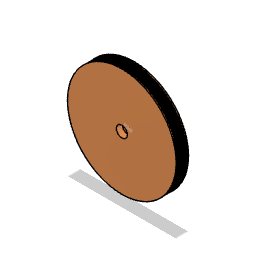
_PULLEY v4.d1a926d5-162d-4901-994e-79e1f1fda4be_LV0.f3d v1 (Autodesk Fusion 360 design; units mm, degrees)
Autodesk Fusion 360 part; units mm, degrees
sketch "Profile" plane through (0, 0, 0) normal (0, 0, 1) x (1, 0, 0) in component "GT2-Pulley"
  circle A0 centre (0, 0) radius 63.662 construction
  circle A1 centre (0, 0) radius 62.658 construction
  line L0 (0, 0) -> (0, 63.662) construction
  line L1 (0, 0) -> (1, 63.6541) construction
  line L2 (0, 0) -> (1.3999, 63.6466) construction
  circle A2 centre (0, 0) radius 63.408 construction
  arc A3 (0.5642, 62.8528) -> (0.9842, 62.6502) centre (0.9929, 63.2052) ccw
  circle A4 centre (0, 0) radius 63.258 construction
  arc A5 (0.4012, 63.2751) -> (0.4738, 63.0018) centre (1.3943, 63.3926) ccw
  arc A6 (0.2529, 63.4075) -> (0, 63.408) centre (0, 0) ccw
  arc A7 (0.4012, 63.2751) -> (0.2529, 63.4075) centre (0.2523, 63.2575) ccw
  arc A8 (0, 63.408) -> (-0.2529, 63.4075) centre (0, 0) ccw
  arc A9 (-0.2529, 63.4075) -> (-0.4012, 63.2751) centre (-0.2523, 63.2575) ccw
  arc A10 (-0.4738, 63.0018) -> (-0.4012, 63.2751) centre (-1.3943, 63.3926) ccw
  arc A11 (-0.9842, 62.6502) -> (-0.5642, 62.8528) centre (-0.9929, 63.2052) ccw
  arc A12 (0.9842, 62.6502) -> (-0.9842, 62.6502) centre (0, 0) ccw
  arc A13 (0.4738, 63.0018) -> (0.5642, 62.8528) centre (1.0358, 63.2404) ccw
  arc A14 (-0.5642, 62.8528) -> (-0.4738, 63.0018) centre (-1.0358, 63.2404) ccw
  point P0 (0.9842, 62.6502)
  point P1 (1.3943, 63.3926)
  point P2 (0, 63.408)
  dimension "d15_2" = 127.324
  dimension "d16_2" = 0.9
  dimension "d17_2" = 0.36
  dimension "d18_2" = 1.004
  dimension "d19_2" = 0.75
  dimension "d20_2" = 0.555
  dimension "d21_2" = 0.15
  dimension "d22_3" = 1
  constraint coincident A0.centre A1.centre
  constraint coincident A0 L0.end
  constraint vertical L0
  constraint coincident A0 L1.end
  constraint coincident A0 L2.end
  constraint concentric A0 A2
  constraint coincident L1 P0
  constraint coincident A1 P0
  constraint coincident L2 P1
  constraint coincident A2 P1
  constraint coincident P0 A3.end
  constraint coincident L1 A3.centre
  constraint concentric A0 A4
  constraint coincident P1 A5.centre
  constraint coincident L0 P2
  constraint coincident A2 P2
  constraint coincident P2 A6.end
  constraint coincident A4 A7.centre
  constraint coincident A5.start A7.start
  constraint tangent A5 A7
  constraint tangent A6 A7
  constraint symmetric L0 A3.start A11.end
  constraint symmetric L0 P0 A11.start
  constraint symmetric L0 A3 A11
  constraint symmetric L0 A5.start A9.end
  constraint symmetric L0 A5.end A10.start
  constraint symmetric L0 A5 A10
  constraint symmetric L0 A6.start A8.end
  constraint symmetric L0 P2 A6.end
  constraint symmetric L0 A6 A8
  constraint symmetric L0 A7 A9
  constraint tangent A5 A13
  constraint tangent A3 A13
  constraint symmetric L0 A13 A14
  measures "d15_2" diameter of A0
  measures "d16_2" angle of L0 L1
  measures "d17_2" angle of L1 L2
  measures "d18_2" distance of A0 A1
  measures "d19_2" distance of A1 A2
  measures "d20_2" radius of A3
  measures "d21_2" distance of A2 A4
  measures "d22_3" radius of A5
sketch "PulleyCore" plane through (0, 0, 0) normal (0, 0, 1) x (1, 0, 0) in component "GT2-Pulley"
  circle A0 centre (0, 0) radius 62.658
  circle A1 centre (0, 0) radius 63.662
extrude "Extrude1" add sketch "PulleyCore" along normal blind 7.2 contours A0 | A1 makes body 1 in component "GT2-Pulley"
extrude "Extrude2" cut sketch "PulleyCore" along normal blind 5.6 bodies 1 in component "GT2-Pulley"
extrude "Extrude3" add sketch "Profile" along normal blind 5.6 separate body makes body 2 in component "GT2-Pulley"
pattern_circular "C-Pattern1" count 200 over 360 about axis through (0, 0, 1.75) along (0, 0, 1) of bodies 2 makes body 3 at (-2.0774, 62.6235, 3.7333) makes body 4 at (-4.698, 62.4816, 3.7333) makes body 5 at (-5.1341, 62.4473, 1.8667) makes body 6 at (-7.9616, 62.1501, 3.7333) makes body 7 at (-9.9099, 61.8694, 3.7333) makes body 8 at (-11.8483, 61.5275, 3.7333) makes body 9 at (-12.9203, 61.3114, 1.8667) makes body 10 at (-15.6883, 60.6622, 3.7333) makes body 11 at (-16.7446, 60.3791, 1.8667) makes body 12 at (-19.4664, 59.5574, 3.7333) makes body 13 at (-21.9433, 58.69, 3.7333) makes body 14 at (-22.3525, 58.5354, 1.8667) makes body 15 at (-24.1801, 57.8044, 1.8667) makes body 16 at (-25.9838, 57.0163, 1.8667) makes body 17 at (-29.1261, 55.477, 3.7333) makes body 18 at (-30.8543, 54.5347, 3.7333) makes body 19 at (-31.2342, 54.318, 1.8667) makes body 20 at (-33.6661, 52.8452, 3.7333) makes body 21 at (-34.5833, 52.2496, 1.8667) makes body 22 at (-36.2074, 51.1375, 1.8667) makes body 23 at (-37.7958, 49.975, 1.8667) makes body 24 at (-39.3469, 48.7631, 1.8667) makes body 25 at (-42.0076, 46.4907, 3.7333) makes body 26 at (-43.4472, 45.1483, 3.7333) makes body 27 at (-44.8439, 43.7613, 3.7333) makes body 28 at (-45.7505, 42.8126, 3.7333) makes body 29 at (-46.4907, 42.0076, 1.8667) makes body 30 at (-48.3484, 39.8554, 3.7333) makes body 31 at (-49.0366, 39.0055, 1.8667) makes body 32 at (-50.7556, 36.7409, 3.7333) makes body 33 at (-51.8846, 35.1285, 3.7333) makes body 34 at (-52.4898, 34.2176, 1.8667) makes body 35 at (-53.9879, 31.8013, 3.7333) makes body 36 at (-55.2723, 29.5127, 3.7333) makes body 37 at (-55.8782, 28.3486, 3.7333) makes body 38 at (-56.3645, 27.3691, 1.8667) makes body 39 at (-57.548, 24.7841, 3.7333) makes body 40 at (-58.2981, 22.9642, 3.7333) makes body 41 at (-58.69, 21.9433, 1.8667) makes body 42 at (-59.625, 19.2583, 3.7333) makes body 43 at (-59.952, 18.2148, 1.8667) makes body 44 at (-60.7166, 15.4765, 3.7333) makes body 45 at (-61.1727, 13.5617, 3.7333) makes body 46 at (-61.4001, 12.492, 1.8667) makes body 47 at (-61.7622, 10.5572, 1.8667) makes body 48 at (-62.0633, 8.612, 1.8667) makes body 49 at (-62.3032, 6.6583, 1.8667) makes body 50 at (-62.5411, 3.8252, 3.7333) makes body 51 at (-62.5983, 2.7331, 1.8667) makes body 52 at (-62.6533, 0.7655, 1.8667) makes body 53 at (-62.6235, -2.0774, 3.7333) makes body 54 at (-62.5777, -3.1701, 1.8667) makes body 55 at (-62.4473, -5.1341, 1.8667) makes body 56 at (-62.1501, -7.9616, 3.7333) makes body 57 at (-61.8694, -9.9099, 3.7333) makes body 58 at (-61.5275, -11.8483, 3.7333) makes body 59 at (-61.125, -13.7751, 3.7333) makes body 60 at (-60.4946, -16.3227, 3.7333) makes body 61 at (-60.3791, -16.7446, 1.8667) makes body 62 at (-59.5574, -19.4664, 3.7333) makes body 63 at (-58.69, -21.9433, 3.7333) makes body 64 at (-58.5354, -22.3525, 1.8667) makes body 65 at (-57.8044, -24.1801, 1.8667) makes body 66 at (-57.0163, -25.9838, 1.8667) makes body 67 at (-55.477, -29.1261, 3.7333) makes body 68 at (-54.5347, -30.8543, 3.7333) makes body 69 at (-53.5387, -32.552, 3.7333) makes body 70 at (-53.3101, -32.925, 1.8667) makes body 71 at (-52.2496, -34.5833, 1.8667) makes body 72 at (-51.1375, -36.2074, 1.8667) makes body 73 at (-49.975, -37.7958, 1.8667) makes body 74 at (-48.7631, -39.3469, 1.8667) makes body 75 at (-46.4907, -42.0076, 3.7333) makes body 76 at (-45.1483, -43.4472, 3.7333) makes body 77 at (-43.7613, -44.8439, 3.7333) makes body 78 at (-42.8126, -45.7505, 3.7333) makes body 79 at (-42.0076, -46.4907, 1.8667) makes body 80 at (-39.3469, -48.7631, 3.7333) makes body 81 at (-37.7958, -49.975, 3.7333) makes body 82 at (-36.2074, -51.1375, 3.7333) makes body 83 at (-35.1285, -51.8846, 3.7333) makes body 84 at (-32.925, -53.3101, 3.7333) makes body 85 at (-31.8013, -53.9879, 3.7333) makes body 86 at (-29.5127, -55.2723, 3.7333) makes body 87 at (-28.3486, -55.8782, 3.7333) makes body 88 at (-27.3691, -56.3645, 1.8667) makes body 89 at (-24.7841, -57.548, 3.7333) makes body 90 at (-22.3525, -58.5354, 3.7333) makes body 91 at (-21.9433, -58.69, 1.8667) makes body 92 at (-20.089, -59.3503, 1.8667) makes body 93 at (-17.376, -60.2005, 3.7333) makes body 94 at (-16.3227, -60.4946, 1.8667) makes body 95 at (-13.5617, -61.1727, 3.7333) makes body 96 at (-12.492, -61.4001, 1.8667) makes body 97 at (-9.0451, -62.0017, 3.7333) makes body 98 at (-8.612, -62.0633, 1.8667) makes body 99 at (-6.6583, -62.3032, 1.8667) makes body 100 at (-3.8252, -62.5411, 3.7333) makes body 101 at (-2.7331, -62.5983, 1.8667) makes body 102 at (-0.7655, -62.6533, 1.8667) makes body 103 at (2.0774, -62.6235, 3.7333) makes body 104 at (4.698, -62.4816, 3.7333) makes body 105 at (6.6583, -62.3032, 3.7333) makes body 106 at (7.9616, -62.1501, 3.7333) makes body 107 at (9.9099, -61.8694, 3.7333) makes body 108 at (12.492, -61.4001, 3.7333) makes body 109 at (12.9203, -61.3114, 1.8667) makes body 110 at (16.3227, -60.4946, 3.7333) makes body 111 at (16.7446, -60.3791, 1.8667) makes body 112 at (19.4664, -59.5574, 3.7333) makes body 113 at (21.9433, -58.69, 3.7333) makes body 114 at (22.3525, -58.5354, 1.8667) makes body 115 at (24.1801, -57.8044, 1.8667) makes body 116 at (25.9838, -57.0163, 1.8667) makes body 117 at (29.1261, -55.477, 3.7333) makes body 118 at (30.8543, -54.5347, 3.7333) makes body 119 at (32.552, -53.5387, 3.7333) makes body 120 at (33.6661, -52.8452, 3.7333) makes body 121 at (34.5833, -52.2496, 1.8667) makes body 122 at (36.2074, -51.1375, 1.8667) makes body 123 at (37.7958, -49.975, 1.8667) makes body 124 at (40.0239, -48.209, 3.7333) makes body 125 at (40.8592, -47.5032, 1.8667) makes body 126 at (43.4472, -45.1483, 3.7333) makes body 127 at (44.8439, -43.7613, 3.7333) makes body 128 at (45.7505, -42.8126, 3.7333) makes body 129 at (46.4907, -42.0076, 1.8667) makes body 130 at (48.7631, -39.3469, 3.7333) makes body 131 at (49.0366, -39.0055, 1.8667) makes body 132 at (51.1375, -36.2074, 3.7333) makes body 133 at (51.8846, -35.1285, 3.7333) makes body 134 at (52.9624, -33.4814, 3.7333) makes body 135 at (53.9879, -31.8013, 3.7333) makes body 136 at (55.2723, -29.5127, 3.7333) makes body 137 at (55.8782, -28.3486, 3.7333) makes body 138 at (56.3645, -27.3691, 1.8667) makes body 139 at (57.548, -24.7841, 3.7333) makes body 140 at (58.2981, -22.9642, 3.7333) makes body 141 at (58.69, -21.9433, 1.8667) makes body 142 at (59.625, -19.2583, 3.7333) makes body 143 at (60.3791, -16.7446, 3.7333) makes body 144 at (60.4946, -16.3227, 1.8667) makes body 145 at (61.1727, -13.5617, 3.7333) makes body 146 at (61.4001, -12.492, 1.8667) makes body 147 at (62.0017, -9.0451, 3.7333) makes body 148 at (62.0633, -8.612, 1.8667) makes body 149 at (62.3032, -6.6583, 1.8667) makes body 150 at (62.5411, -3.8252, 3.7333) makes body 151 at (62.5983, -2.7331, 1.8667) makes body 152 at (62.6579, 0.1094, 3.7333) makes body 153 at (62.6235, 2.0774, 3.7333) makes body 154 at (62.5777, 3.1701, 1.8667) makes body 155 at (62.3032, 6.6583, 3.7333) makes body 156 at (62.1501, 7.9616, 3.7333) makes body 157 at (61.8694, 9.9099, 3.7333) makes body 158 at (61.5275, 11.8483, 3.7333) makes body 159 at (61.125, 13.7751, 3.7333) makes body 160 at (60.4946, 16.3227, 3.7333) makes body 161 at (60.3791, 16.7446, 1.8667) makes body 162 at (59.5574, 19.4664, 3.7333) makes body 163 at (59.2086, 20.5028, 1.8667) makes body 164 at (58.5354, 22.3525, 1.8667) makes body 165 at (57.8044, 24.1801, 1.8667) makes body 166 at (57.0163, 25.9838, 1.8667) makes body 167 at (55.477, 29.1261, 3.7333) makes body 168 at (54.5347, 30.8543, 3.7333) makes body 169 at (53.5387, 32.552, 3.7333) makes body 170 at (52.8452, 33.6661, 3.7333) makes body 171 at (52.2496, 34.5833, 1.8667) makes body 172 at (51.1375, 36.2074, 1.8667) makes body 173 at (49.975, 37.7958, 1.8667) makes body 174 at (48.209, 40.0239, 3.7333) makes body 175 at (46.4907, 42.0076, 3.7333) makes body 176 at (45.1483, 43.4472, 3.7333) makes body 177 at (43.7613, 44.8439, 3.7333) makes body 178 at (43.4472, 45.1483, 1.8667) makes body 179 at (41.3544, 47.0727, 3.7333) makes body 180 at (39.3469, 48.7631, 3.7333) makes body 181 at (39.0055, 49.0366, 1.8667) makes body 182 at (36.2074, 51.1375, 3.7333) makes body 183 at (35.1285, 51.8846, 3.7333) makes body 184 at (34.2176, 52.4898, 1.8667) makes body 185 at (31.8013, 53.9879, 3.7333) makes body 186 at (29.5127, 55.2723, 3.7333) makes body 187 at (28.3486, 55.8782, 3.7333) makes body 188 at (27.3691, 56.3645, 1.8667) makes body 189 at (24.7841, 57.548, 3.7333) makes body 190 at (22.9642, 58.2981, 3.7333) makes body 191 at (21.9433, 58.69, 1.8667) makes body 192 at (20.089, 59.3503, 1.8667) makes body 193 at (16.7446, 60.3791, 3.7333) makes body 194 at (15.4765, 60.7166, 3.7333) makes body 195 at (13.5617, 61.1727, 3.7333) makes body 196 at (11.6335, 61.5685, 3.7333) makes body 197 at (10.5572, 61.7622, 1.8667) makes body 198 at (8.612, 62.0633, 1.8667) makes body 199 at (6.6583, 62.3032, 1.8667) makes body 200 at (3.1701, 62.5777, 3.7333) makes body 201 at (2.7331, 62.5983, 1.8667) in component "GT2-Pulley"
combine "Combine1" operation add target body 190 tool bodies 119 56 192 194 74 116 117 79 156 64 122 70 110 2 118 160 61 113 54 109 161 163 58 114 107 169 55 103 181 81 53 106 177 115 112 67 131 158 164 75 120 78 102 153 170 145 66 104 60 125 69 150 123 180 179 72 155 126 80 172 124 57 105 189 187 108 111 63 199 65 121 196 182 68 195 35 191 76 36 185 77 38 39 201 193 5 40 188 6 8 42 46 186 92 88 140 157 167 152 154 96 174 97 1 95 146 147 101 148 178 136 85 176 175 84 143 139 168 87 137 144 62 141 59 100 149 83 128 89 151 91 129 134 135 93 94 73 71 200 45 10 9 49 12 51 19 17 52 32 127 7 48 31 34 130 13 47 14 33 20 22 37 21 24 29 41 43 44 4 11 50 15 30 16 184 18 198 197 25 3 183 23 26 86 28 27 82 99 133 173 90 98 138 142 132 171 162 165 166 159 in component "GT2-Pulley"
mirror "Mirror1" about plane through (0, 0, 0) normal (0, 0, -1) of bodies 190 makes body 202 in component "GT2-Pulley"
hole "Hole1" at (0, 0, 7.2) direction (0, 0, -1) diameter 13 depth 30 tip angle 118 bodies 190 202 in component "GT2-Pulley"
component "GT2-Pulley" placed x (0.971926, -0.235285, 0) y (0.235285, 0.971926, 0) z (0, 0, 1) at (60, 30.8003, 174.3898)
equation "d15_2 = PulleyDia"
equation "d16_2 = ToothAng / 2"
equation "d17_2 = TransOffsetAngle"
equation "d18_2 = PLD + ToothHeight"
equation "d19_2 = ToothHeight"
equation "d20_2 = Root_Radius"
equation "d21_2 = Shoulder_Radius"
equation "d22_3 = Trans_Radius"
equation "d31_2 = NumTeeth"
equation "NumTeeth = 200"
equation "ToothPitch = 2 mm"
equation "PulleyDia = NumTeeth * ToothPitch / PI"
equation "ToothAng = ( 360 / NumTeeth ) * 1 deg"
equation "TransOffsetAngle = ToothAng * 0.2"
equation "Shoulder_Radius = 0.15 mm"
equation "Root_Radius = 0.555 mm"
equation "Trans_Radius = 1 mm"
equation "ToothHeight = 0.75 mm"
equation "PLD = 0.254 mm"
